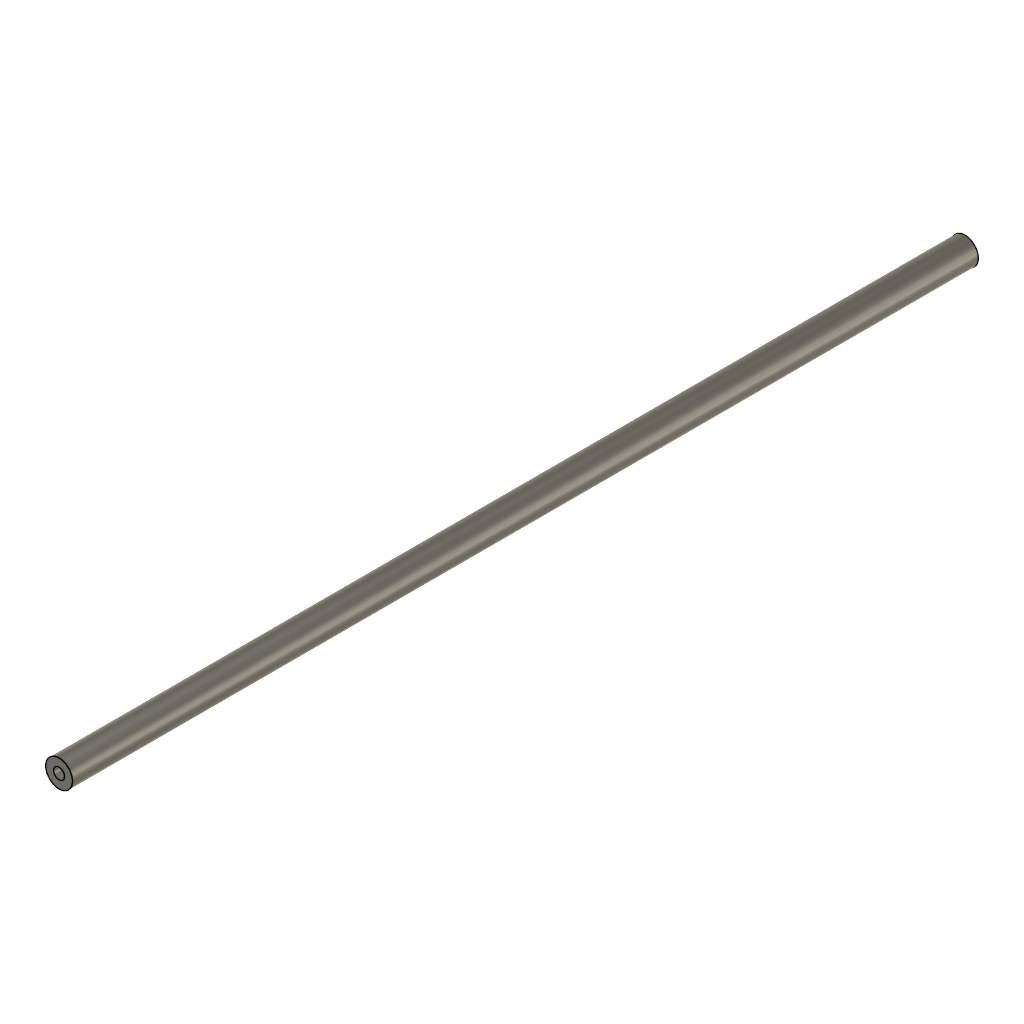
sliding rod left (Autodesk Fusion 360 design; units mm, degrees)
part number: 2026-11-08-18-01-31-957
Autodesk Fusion 360 part; units mm, degrees
sketch "Sketch1" plane through (0, 97, 0) normal (0, 1, 0) x (-1, 0, 0)
  line L0 (-3, 5) -> (-16.5, 5)
  line L1 (-16.5, 5) -> (-16.5, -12)
  line L2 (-16.5, -12) -> (-3, -12)
  line L3 (-3, -12) -> (-3, 5)
  circle A0 centre (-9.75, 0) radius 2
  circle A1 centre (-9.75, 0) radius 1
  dimension "d1" = 4
  dimension "d2" = 2
  constraint concentric A0 A1
  measures "d1" diameter of A0
  measures "d2" diameter of A1
sketch "Sketch2" plane through (0, -43.5, 0) normal (0, -1, 0) x (1, 0, 0)
  line L0 (3, 5) -> (3, -12)
  line L1 (3, -12) -> (16.5, -12)
  line L2 (16.5, -12) -> (16.5, 5)
  line L3 (16.5, 5) -> (3, 5)
  circle A0 centre (9.75, 0) radius 1
  dimension "d3" = 2
  measures "d3" diameter of A0
sketch "Sketch3" plane through (0, 92.5, 0) normal (0, -1, 0) x (1, 0, 0)
  line L0 (16.5, 5) -> (3, 5)
  line L1 (3, 5) -> (3, -12)
  line L2 (3, -12) -> (16.5, -12)
  line L3 (16.5, -12) -> (16.5, 5)
  circle A0 centre (9.75, 0) radius 4
  circle A1 centre (9.75, 0) radius 2
  dimension "d4" = 8
  dimension "d5" = 4
  constraint concentric A0 A1
  measures "d4" diameter of A0
  measures "d5" diameter of A1
extrude "Extrude1" add sketch "Sketch3" along normal blind 133.5 contours A1
extrude "Extrude2" cut sketch "Sketch1" against normal blind 6 contours A1
extrude "Extrude3" cut sketch "Sketch1" against normal blind 8 contours A1
extrude "Extrude4" cut sketch "Sketch2" against normal blind 6 contours A0
thread "Thread1" "ISO Metric profile 2.0 M2x0.4 M2x0.4 6H" major diameter 2.074 minor diameter 1.623 pitch 0.4 angle 60 resizes the face on face at (10.745, -39.8333, -0.0996)
thread "Thread2" "ISO Metric profile 2.0 M2x0.4 M2x0.4 6H" major diameter 2.074 minor diameter 1.623 pitch 0.4 angle 60 resizes the face on face at (8.755, 91.3333, -0.0996)
